internal_layout_candidate_v01_NOT_FOR_MANUFACTURE (Autodesk Fusion 360 design; units mm, degrees)
part number: 2026-11-07-00-59-36-641
part number: 2026-11-07-00-59-36-822
part number: 2026-11-07-00-59-37-127
part number: 2026-11-07-00-59-37-171
part number: 2026-11-07-00-59-37-525
part number: 2026-11-07-01-42-10-019
part number: 2026-11-07-01-42-10-090
part number: 2026-11-07-01-42-10-141
part number: 2026-11-07-01-42-10-249
part number: 2026-11-07-01-42-10-310
part number: 2026-11-07-01-42-10-381
Autodesk Fusion 360 part; units mm, degrees
sketch "スケッチ1" plane through (0, 0, 0) normal (0, 0, 1) x (1, 0, 0) in component "PCB_L_v2_reference_NOT_VERIFIED"
  arc A0 (-48.47, 6.054) -> (-49.47, 7.054) centre (-49.47, 6.054) ccw
  line L0 (-47.47, 4.554) -> (-30.42, 4.554)
  line L1 (-65.52, 7.054) -> (-49.47, 7.054)
  line L2 (-68.52, -72.846) -> (-85.57, -72.846)
  arc A1 (-43.47, -55.096) -> (-44.47, -54.096) centre (-44.47, -55.096) ccw
  arc A2 (12.4958, -87.3783) -> (13.765, -86.7762) centre (12.8253, -86.4342) ccw
  line L3 (-43.47, -76.846) -> (-43.47, -55.096)
  line L4 (10.0762, -0.946) -> (10.0762, -1.946)
  line L5 (-103.62, -4.646) -> (-86.57, -4.646)
  arc A3 (-29.42, 3.054) -> (-28.42, 2.054) centre (-28.42, 3.054) ccw
  arc A4 (-29.42, 3.554) -> (-30.42, 4.554) centre (-30.42, 3.554) ccw
  arc A5 (-85.57, -72.846) -> (-86.57, -73.846) centre (-85.57, -73.846) ccw
  arc A6 (-87.57, -79.846) -> (-86.57, -78.846) centre (-87.57, -78.846) ccw
  arc A7 (-68.52, -72.846) -> (-67.52, -71.846) centre (-68.52, -71.846) ccw
  line L6 (-25.5816, -77.846) -> (-42.47, -77.846)
  arc A8 (-104.62, -78.846) -> (-103.62, -79.846) centre (-103.62, -78.846) ccw
  arc A9 (-25.2605, -77.8719) -> (-25.5816, -77.846) centre (-25.5815, -79.8459) ccw
  line L7 (-48.47, 6.054) -> (-48.47, 5.554)
  arc A10 (-10.37, 1.054) -> (-9.37, 0.054) centre (-9.37, 1.054) ccw
  line L8 (-104.62, -78.846) -> (-104.62, -5.646)
  line L9 (-44.47, -54.096) -> (-47.47, -54.096)
  line L10 (-66.52, 3.354) -> (-66.52, 6.054)
  line L11 (-29.42, 3.554) -> (-29.42, 3.054)
  line L12 (-87.57, -79.846) -> (-103.62, -79.846)
  line L13 (-5.7378, -81.0467) -> (-25.2605, -77.8719)
  line L14 (19.2592, -71.6805) -> (13.765, -86.7762)
  arc A11 (-48.47, 5.554) -> (-47.47, 4.554) centre (-47.47, 5.554) ccw
  arc A12 (-66.52, -68.146) -> (-67.52, -69.146) centre (-66.52, -69.146) ccw
  arc A13 (19.2592, -71.6805) -> (18.6615, -70.3988) centre (18.3195, -71.3385) ccw
  arc A14 (-47.47, -54.096) -> (-48.47, -55.096) centre (-47.47, -55.096) ccw
  line L15 (-28.42, 2.054) -> (-11.37, 2.054)
  line L16 (-85.57, -3.646) -> (-85.57, 1.354)
  line L17 (-49.47, -68.146) -> (-66.52, -68.146)
  line L18 (-84.57, 2.354) -> (-67.52, 2.354)
  arc A15 (10.0762, -0.946) -> (9.0762, 0.054) centre (9.0762, -0.946) ccw
  arc A16 (-65.52, 7.054) -> (-66.52, 6.054) centre (-65.52, 6.054) ccw
  line L19 (-86.57, -73.846) -> (-86.57, -78.846)
  line L20 (-48.47, -55.096) -> (-48.47, -67.146)
  arc A17 (-84.57, 2.354) -> (-85.57, 1.354) centre (-84.57, 1.354) ccw
  arc A18 (-103.62, -4.646) -> (-104.62, -5.646) centre (-103.6199, -5.6461) ccw
  line L21 (-9.37, 0.054) -> (9.0762, 0.054)
  arc A19 (-43.47, -76.846) -> (-42.47, -77.846) centre (-42.47, -76.846) ccw
  arc A20 (-49.47, -68.146) -> (-48.47, -67.146) centre (-49.47, -67.146) ccw
  arc A21 (-86.57, -4.646) -> (-85.57, -3.646) centre (-86.57, -3.646) ccw
  arc A22 (10.0762, -66.5739) -> (10.7342, -67.5136) centre (11.0762, -66.5739) ccw
  line L22 (12.4958, -87.3783) -> (-5.3997, -81.1324)
  line L23 (10.7342, -67.5136) -> (18.6615, -70.3988)
  arc A23 (-10.37, 1.054) -> (-11.37, 2.054) centre (-11.37, 1.054) ccw
  line L24 (-67.52, -69.146) -> (-67.52, -71.846)
  arc A24 (-67.52, 2.354) -> (-66.52, 3.354) centre (-67.52, 3.354) ccw
  arc A25 (-5.3997, -81.1324) -> (-5.7378, -81.0467) centre (-6.0588, -83.0207) ccw
  line L25 (10.0762, -1.946) -> (10.0762, -66.5739)
  circle A26 centre (-3.01, -75.606) radius 2.15
  circle A27 centre (-84.95, -54.286) radius 2.15
  circle A28 centre (-23.77, -71.026) radius 2.15
  circle A29 centre (-27.83, -35.536) radius 2.15
  circle A30 centre (-84.96, -16.186) radius 2.15
  circle A31 centre (5.5307, -63.001) radius 2.15
  circle A32 centre (-30, -13.986) radius 2.15
extrude "Reference_PCB_thickness_1p6" add sketch "スケッチ1" along normal blind 1.6 makes body 1 in component "PCB_L_v2_reference_NOT_VERIFIED"
sketch "スケッチ2" plane through (0, 0, 0) normal (0, 0, 1) x (1, 0, 0) in component "PCB_L_v2_reference_NOT_VERIFIED"
  circle A0 centre (-38.4693, -23.4563) radius 2.5 construction
  circle A1 centre (-19.4193, -25.9565) radius 2.5 construction
  circle A2 centre (-57.5437, -59.036) radius 2.5 construction
  circle A3 centre (7.962, -76.1269) radius 2.5 construction
  circle A4 centre (-19.4193, -45.0065) radius 2.5 construction
  circle A5 centre (-95.6193, -13.606) radius 2.5 construction
  circle A6 centre (-38.4693, -4.4062) radius 2.5 construction
  circle A7 centre (-57.5193, -20.956) radius 2.5 construction
  circle A8 centre (-57.5193, -1.906) radius 2.5 construction
  circle A9 centre (-38.4693, -42.5063) radius 2.5 construction
  circle A10 centre (-57.5193, -40.006) radius 2.5 construction
  circle A11 centre (-76.5693, -6.6065) radius 2.5 construction
  circle A12 centre (-95.6193, -70.756) radius 2.5 construction
  circle A13 centre (-19.4193, -6.9065) radius 2.5 construction
  circle A14 centre (-0.3693, -49.531) radius 2.5 construction
  circle A15 centre (-76.5693, -25.6565) radius 2.5 construction
  circle A16 centre (-0.3593, -30.486) radius 2.5 construction
  circle A17 centre (-95.6193, -51.706) radius 2.5 construction
  circle A18 centre (-95.6193, -32.656) radius 2.5 construction
  circle A19 centre (-34.4523, -68.8313) radius 2.5 construction
  circle A20 centre (-76.5693, -63.7565) radius 2.5 construction
  circle A21 centre (-76.5693, -44.7065) radius 2.5 construction
  circle A22 centre (-13.1151, -70.5713) radius 2.5 construction
sketch "スケッチ1 (2)" plane through (0, 0, 0) normal (0, 0, 1) x (1, 0, 0) in component "Battery_L_30x20x4_CANDIDATE_UNVERIFIED"
  line L0 (0, 30) -> (30, 30)
  line L1 (30, 30) -> (30, 50)
  line L2 (30, 50) -> (0, 50)
  line L3 (0, 50) -> (0, 30)
extrude "Battery_body_4mm_approximate" add sketch "スケッチ1 (2)" along normal blind 4 separate body makes body 2 in component "Battery_L_30x20x4_CANDIDATE_UNVERIFIED"
sketch "スケッチ1 (3)" plane through (0, 0, 0) normal (0, 0, 1) x (1, 0, 0) in component "PCB_R_v2_reference_NOT_VERIFIED"
  line L0 (3.7236, -81.4944) -> (-12.4402, -87.3769)
  arc A0 (29.8044, -52.6125) -> (28.8361, -53.3625) centre (29.8044, -53.6125) ccw
  line L1 (66.7593, -54.1125) -> (66.7593, -53.6125)
  arc A1 (-10.686, -67.5299) -> (-10.028, -66.5902) centre (-11.028, -66.5902) ccw
  line L2 (11.4179, 2.0375) -> (28.4679, 2.0375)
  arc A2 (28.4679, 2.0375) -> (29.4679, 3.0375) centre (28.4679, 3.0375) ccw
  arc A3 (104.6679, -5.6625) -> (103.6679, -4.6625) centre (103.668, -5.6625) ccw
  arc A4 (21.2554, -54.1125) -> (20.2554, -55.1125) centre (21.2554, -55.1125) ccw
  arc A5 (66.5679, 6.0375) -> (65.5679, 7.0375) centre (65.5679, 6.0375) ccw
  arc A6 (-18.6136, -70.4153) -> (-19.2113, -71.697) centre (-18.2716, -71.355) ccw
  line L3 (67.5679, 2.3375) -> (84.6179, 2.3375)
  line L4 (48.5179, 5.5375) -> (48.5179, 6.0375)
  line L5 (30.4679, 4.5375) -> (47.5179, 4.5375)
  arc A7 (49.5179, 7.0375) -> (48.5179, 6.0375) centre (49.5179, 6.0375) ccw
  line L6 (86.6179, -4.6625) -> (103.6679, -4.6625)
  line L7 (-18.6136, -70.4153) -> (-10.686, -67.5299)
  line L8 (76.2293, -55.1125) -> (67.7593, -55.1125)
  line L9 (85.6179, 1.3375) -> (85.6179, -3.6625)
  arc A8 (66.7593, -54.1125) -> (67.7593, -55.1125) centre (67.7593, -54.1125) ccw
  arc A9 (27.8679, -54.1125) -> (28.8361, -53.3625) centre (27.8679, -53.1125) ccw
  arc A10 (9.4179, 0.0375) -> (10.4179, 1.0375) centre (9.4179, 1.0375) ccw
  line L10 (65.7593, -52.6125) -> (29.8044, -52.6125)
  line L11 (-10.028, -66.5902) -> (-10.028, -52.6125)
  line L12 (29.4679, 3.0375) -> (29.4679, 3.5375)
  line L13 (20.301, -60.4398) -> (23.2168, -76.973)
  arc A11 (103.6679, -79.8625) -> (104.6679, -78.8625) centre (103.6679, -78.8625) ccw
  line L14 (27.8679, -54.1125) -> (21.2554, -54.1125)
  line L15 (-10.028, -52.6125) -> (-10.028, -0.9625)
  arc A12 (47.5179, 4.5375) -> (48.5179, 5.5375) centre (47.5179, 5.5375) ccw
  line L16 (-13.7219, -86.7792) -> (-19.2113, -71.697)
  arc A13 (4.3954, -81.3142) -> (3.7236, -81.4944) centre (5.0915, -85.2531) ccw
  line L17 (103.6679, -79.8625) -> (77.7293, -79.8625)
  line L18 (-9.028, 0.0375) -> (9.4179, 0.0375)
  arc A14 (77.2293, -56.1125) -> (76.2293, -55.1125) centre (76.2293, -56.1125) ccw
  arc A15 (85.6179, 1.3375) -> (84.6179, 2.3375) centre (84.618, 1.3375) ccw
  arc A16 (85.6179, -3.6625) -> (86.6179, -4.6625) centre (86.618, -3.6625) ccw
  arc A17 (20.2554, -59.9187) -> (20.301, -60.4398) centre (23.2554, -59.9187) ccw
  arc A18 (-13.7219, -86.7792) -> (-12.4402, -87.3769) centre (-12.7822, -86.4372) ccw
  arc A19 (66.7593, -53.6125) -> (65.7593, -52.6125) centre (65.7593, -53.6125) ccw
  arc A20 (77.2293, -79.3625) -> (77.7293, -79.8625) centre (77.7292, -79.3626) ccw
  line L19 (49.5179, 7.0375) -> (65.5679, 7.0375)
  line L20 (22.406, -78.1315) -> (4.3954, -81.3142)
  line L21 (77.2293, -79.3625) -> (77.2293, -56.1125)
  line L22 (66.5679, 6.0375) -> (66.5679, 3.3375)
  arc A21 (66.5679, 3.3375) -> (67.5679, 2.3375) centre (67.5679, 3.3375) ccw
  arc A22 (11.4179, 2.0375) -> (10.4179, 1.0375) centre (11.4179, 1.0375) ccw
  arc A23 (30.4679, 4.5375) -> (29.4679, 3.5375) centre (30.4679, 3.5375) ccw
  line L23 (20.2554, -55.1125) -> (20.2554, -59.9187)
  arc A24 (22.406, -78.1315) -> (23.2168, -76.973) centre (22.232, -77.1467) ccw
  arc A25 (-9.028, 0.0375) -> (-10.028, -0.9625) centre (-9.028, -0.9625) ccw
  line L24 (104.6679, -5.6625) -> (104.6679, -78.8625)
  circle A26 centre (-5.574, -62.875) radius 2.15
  circle A27 centre (85.401, -54.3) radius 2.15
  circle A28 centre (2.771, -75.62) radius 2.15
  circle A29 centre (85.431, -16.21) radius 2.15
  circle A30 centre (28.671, -46.92) radius 2.15
  circle A31 centre (29.071, -14.01) radius 2.15
extrude "Reference_PCB_thickness_1p6'" add sketch "スケッチ1 (3)" along normal blind 1.6 separate body makes body 3 in component "PCB_R_v2_reference_NOT_VERIFIED"
sketch "スケッチ2 (2)" plane through (0, 0, 0) normal (0, 0, 1) x (1, 0, 0) in component "PCB_R_v2_reference_NOT_VERIFIED"
  circle A0 centre (19.431, -6.9292) radius 2.5 construction
  circle A1 centre (0.381, -49.5537) radius 2.5 construction
  circle A2 centre (76.581, -44.7292) radius 2.5 construction
  circle A3 centre (12.8578, -70.5702) radius 2.5 construction
  circle A4 centre (76.581, -6.6292) radius 2.5 construction
  circle A5 centre (95.631, -13.6287) radius 2.5 construction
  circle A6 centre (57.531, -40.0287) radius 2.5 construction
  circle A7 centre (-8.0339, -76.1493) radius 2.5 construction
  circle A8 centre (95.631, -51.7287) radius 2.5 construction
  circle A9 centre (95.631, -70.7787) radius 2.5 construction
  circle A10 centre (19.431, -45.0292) radius 2.5 construction
  circle A11 centre (38.481, -42.529) radius 2.5 construction
  circle A12 centre (57.531, -20.9787) radius 2.5 construction
  circle A13 centre (38.481, -4.429) radius 2.5 construction
  circle A14 centre (38.481, -23.479) radius 2.5 construction
  circle A15 centre (57.531, -1.9287) radius 2.5 construction
  circle A16 centre (0.381, -30.4537) radius 2.5 construction
  circle A17 centre (19.431, -25.9792) radius 2.5 construction
  circle A18 centre (95.631, -32.6787) radius 2.5 construction
  circle A19 centre (76.581, -25.6792) radius 2.5 construction
sketch "スケッチ1 (4)" plane through (0, 0, 0) normal (0, 0, 1) x (1, 0, 0) in component "Battery_R_30x20x4_CANDIDATE_UNVERIFIED"
  line L0 (0, 30) -> (30, 30)
  line L1 (30, 30) -> (30, 50)
  line L2 (30, 50) -> (0, 50)
  line L3 (0, 50) -> (0, 30)
extrude "Battery_body_4mm_approximate'" add sketch "スケッチ1 (4)" along normal blind 4 separate body makes body 4 in component "Battery_R_30x20x4_CANDIDATE_UNVERIFIED"
sketch "スケッチ1 (5)" plane through (0, 0, 0) normal (0, 0, 1) x (1, 0, 0) in component "Battery_L_32x22x5p5_INSTALLATION_ALLOWANCE_ASSUMED"
  line L0 (0, 0) -> (32, 0)
  line L1 (32, 0) -> (32, 22)
  line L2 (32, 22) -> (0, 22)
  line L3 (0, 22) -> (0, 0)
extrude "押し出し1" add sketch "スケッチ1 (5)" along normal blind 5.5 separate body makes body 5 in component "Battery_L_32x22x5p5_INSTALLATION_ALLOWANCE_ASSUMED"
sketch "スケッチ1 (6)" plane through (0, 0, 0) normal (0, 0, 1) x (1, 0, 0) in component "PCB_L_UNDERSIDE_3mm_RESERVATION_NOT_COMPLETE_PARTS"
  line L0 (0, 0) -> (123.9395, 0)
  line L1 (123.9395, 0) -> (123.9395, 94.4882)
  line L2 (123.9395, 94.4882) -> (0, 94.4882)
  line L3 (0, 94.4882) -> (0, 0)
extrude "押し出し1'" add sketch "スケッチ1 (6)" along normal blind 3 separate body makes body 6 in component "PCB_L_UNDERSIDE_3mm_RESERVATION_NOT_COMPLETE_PARTS"
sketch "スケッチ1 (7)" plane through (0, 0, 0) normal (0, 0, 1) x (1, 0, 0) in component "Screw_L_M2_EXTERNAL_AXES_ONLY_NOT_FINAL"
  circle A0 centre (-109.62, -7.946) radius 1 construction
  circle A1 centre (-109.62, -7.946) radius 3 construction
  circle A2 centre (24.3195, -7.946) radius 1 construction
  circle A3 centre (24.3195, -7.946) radius 3 construction
  circle A4 centre (-109.62, -72.4342) radius 1 construction
  circle A5 centre (-109.62, -72.4342) radius 3 construction
  circle A6 centre (24.3195, -72.4342) radius 1 construction
  circle A7 centre (24.3195, -72.4342) radius 3 construction
sketch "スケッチ1 (8)" plane through (0, 0, 0) normal (0, 0, 1) x (1, 0, 0) in component "Battery_R_32x22x5p5_INSTALLATION_ALLOWANCE_ASSUMED"
  line L0 (0, 0) -> (32, 0)
  line L1 (32, 0) -> (32, 22)
  line L2 (32, 22) -> (0, 22)
  line L3 (0, 22) -> (0, 0)
extrude "押し出し1''" add sketch "スケッチ1 (8)" along normal blind 5.5 separate body makes body 7 in component "Battery_R_32x22x5p5_INSTALLATION_ALLOWANCE_ASSUMED"
sketch "スケッチ1 (9)" plane through (0, 0, 0) normal (0, 0, 1) x (1, 0, 0) in component "PCB_R_UNDERSIDE_3mm_RESERVATION_NOT_COMPLETE_PARTS"
  line L0 (0, 0) -> (123.9395, 0)
  line L1 (123.9395, 0) -> (123.9395, 94.4747)
  line L2 (123.9395, 94.4747) -> (0, 94.4747)
  line L3 (0, 94.4747) -> (0, 0)
extrude "押し出し1'''" add sketch "スケッチ1 (9)" along normal blind 3 separate body makes body 8 in component "PCB_R_UNDERSIDE_3mm_RESERVATION_NOT_COMPLETE_PARTS"
sketch "スケッチ1 (10)" plane through (0, 0, 0) normal (0, 0, 1) x (1, 0, 0) in component "Screw_R_M2_EXTERNAL_AXES_ONLY_NOT_FINAL"
  circle A0 centre (-24.2716, -7.9625) radius 1 construction
  circle A1 centre (-24.2716, -7.9625) radius 3 construction
  circle A2 centre (109.6679, -7.9625) radius 1 construction
  circle A3 centre (109.6679, -7.9625) radius 3 construction
  circle A4 centre (-24.2716, -72.4372) radius 1 construction
  circle A5 centre (-24.2716, -72.4372) radius 3 construction
  circle A6 centre (109.6679, -72.4372) radius 1 construction
  circle A7 centre (109.6679, -72.4372) radius 3 construction
component "PCB_L_v2_reference_NOT_VERIFIED" placed x (1, 0, 0) y (0, 1, 0) z (0, 0, 1) at (0, 0, 0)
component "Battery_L_30x20x4_CANDIDATE_UNVERIFIED" placed x (1, 0, 0) y (0, 1, 0) z (0, 0, 1) at (-65, -80, -8)
component "PCB_R_v2_reference_NOT_VERIFIED" placed x (1, 0, 0) y (0, 1, 0) z (0, 0, 1) at (160, 0, 0)
component "Battery_R_30x20x4_CANDIDATE_UNVERIFIED" placed x (1, 0, 0) y (0, 1, 0) z (0, 0, 1) at (195, -80, -8)
component "Battery_L_32x22x5p5_INSTALLATION_ALLOWANCE_ASSUMED" placed x (1, 0, 0) y (0, 1, 0) z (0, 0, 1) at (-66, -51, -9)
component "PCB_L_UNDERSIDE_3mm_RESERVATION_NOT_COMPLETE_PARTS" placed x (1, 0, 0) y (0, 1, 0) z (0, 0, 1) at (-104.62, -87.4342, -3)
component "Screw_L_M2_EXTERNAL_AXES_ONLY_NOT_FINAL" placed x (1, 0, 0) y (0, 1, 0) z (0, 0, 1) at (0, 0, 0)
component "Battery_R_32x22x5p5_INSTALLATION_ALLOWANCE_ASSUMED" placed x (1, 0, 0) y (0, 1, 0) z (0, 0, 1) at (194, -51, -9)
component "PCB_R_UNDERSIDE_3mm_RESERVATION_NOT_COMPLETE_PARTS" placed x (1, 0, 0) y (0, 1, 0) z (0, 0, 1) at (140.7284, -87.4372, -3)
component "Screw_R_M2_EXTERNAL_AXES_ONLY_NOT_FINAL" placed x (1, 0, 0) y (0, 1, 0) z (0, 0, 1) at (160, 0, 0)
hidden bodies 5 6 7 8
named bodies: "PCB_envelope_mount_holes_only", "Battery_L_32x22x5p5_INSTALLATION_ALLOWANCE_ASSUMED", "PCB_L_UNDERSIDE_3mm_RESERVATION_NOT_COMPLETE_PARTS", "Battery_R_32x22x5p5_INSTALLATION_ALLOWANCE_ASSUMED", "PCB_R_UNDERSIDE_3mm_RESERVATION_NOT_COMPLETE_PARTS"
